Autodesk Fusion 360 part; units mm, degrees
(part 2 of 3)
ref_plane "WorkPlane21" through (0, 0, 1.55) normal (0, 0, 1) x (1, 0, 0) in component "02 Rear cover - ESP32 mounting and concealed button access"
sketch "right lower rear registration key profile" plane through (0, 0, 1.55) normal (0, 0, 1) x (1, 0, 0) in component "02 Rear cover - ESP32 mounting and concealed button access"
  line L0 (24.61, -15.45) -> (25.86, -15.45)
  line L1 (25.86, -15.45) -> (25.86, -12.85)
  line L2 (25.86, -12.85) -> (24.61, -12.85)
  line L3 (24.61, -12.85) -> (24.61, -15.45)
  dimension "d485" = 24.61
  dimension "d486" = 15.45
  dimension "d487" = 1.25
  dimension "d488" = 2.6
  constraint horizontal L0
  constraint horizontal L2
  constraint vertical L1
  constraint vertical L3
  measures "d485" horizontal distance of origin L0.start
  measures "d486" vertical distance of origin L0.start
  measures "d487" horizontal distance of L0.start L0.end
  measures "d488" vertical distance of L0.end L1.end
extrude "right lower rear registration key" add sketch "right lower rear registration key profile" along normal blind 1.15 bodies 2 in component "02 Rear cover - ESP32 mounting and concealed button access"
ref_plane "WorkPlane22" through (0, 0, 1.55) normal (0, 0, 1) x (1, 0, 0) in component "02 Rear cover - ESP32 mounting and concealed button access"
sketch "right upper rear registration key profile" plane through (0, 0, 1.55) normal (0, 0, 1) x (1, 0, 0) in component "02 Rear cover - ESP32 mounting and concealed button access"
  line L0 (24.61, 12.85) -> (25.86, 12.85)
  line L1 (25.86, 12.85) -> (25.86, 15.45)
  line L2 (25.86, 15.45) -> (24.61, 15.45)
  line L3 (24.61, 15.45) -> (24.61, 12.85)
  dimension "d493" = 24.61
  dimension "d494" = 12.85
  dimension "d495" = 1.25
  dimension "d496" = 2.6
  constraint horizontal L0
  constraint horizontal L2
  constraint vertical L1
  constraint vertical L3
  measures "d493" horizontal distance of origin L0.start
  measures "d494" vertical distance of origin L0.start
  measures "d495" horizontal distance of L0.start L0.end
  measures "d496" vertical distance of L0.end L1.end
extrude "right upper rear registration key" add sketch "right upper rear registration key profile" along normal blind 1.15 bodies 2 in component "02 Rear cover - ESP32 mounting and concealed button access"
sketch "USB-C plug relief at rear edge profile" plane through (0, 0, 0) normal (0, 0, 1) x (1, 0, 0) in component "02 Rear cover - ESP32 mounting and concealed button access"
  line L0 (26.81, -7) -> (28.71, -7)
  line L1 (28.71, -7) -> (28.71, 7)
  line L2 (28.71, 7) -> (26.81, 7)
  line L3 (26.81, 7) -> (26.81, -7)
  dimension "d499" = 26.81
  dimension "d500" = 7
  dimension "d501" = 1.9
  dimension "d502" = 14
  constraint horizontal L0
  constraint horizontal L2
  constraint vertical L1
  constraint vertical L3
  measures "d499" horizontal distance of origin L0.start
  measures "d500" vertical distance of origin L0.start
  measures "d501" horizontal distance of L0.start L0.end
  measures "d502" vertical distance of L0.end L1.end
extrude "USB-C plug relief at rear edge" cut sketch "USB-C plug relief at rear edge profile" along normal blind 1.55 bodies 2 in component "02 Rear cover - ESP32 mounting and concealed button access"
ref_plane "WorkPlane1" through (0, 0, 12.25) normal (0, 0, 1) x (1, 0, 0) in component "90 Reference - Handson DSP1170 4-pin OLED"
sketch "OLED carrier PCB profile" plane through (0, 0, 12.25) normal (0, 0, 1) x (1, 0, 0) in component "90 Reference - Handson DSP1170 4-pin OLED"
  line L0 (-17.7, -16.75) -> (17.7, -16.75)
  line L1 (17.7, -16.75) -> (17.7, 16.75)
  line L2 (17.7, 16.75) -> (-17.7, 16.75)
  line L3 (-17.7, 16.75) -> (-17.7, -16.75)
  dimension "d507" = 17.7
  dimension "d508" = 16.75
  dimension "d509" = 35.4
  dimension "d510" = 33.5
  constraint horizontal L0
  constraint horizontal L2
  constraint vertical L1
  constraint vertical L3
  measures "d507" horizontal distance of origin L0.start
  measures "d508" vertical distance of origin L0.start
  measures "d509" horizontal distance of L0.start L0.end
  measures "d510" vertical distance of L0.end L1.end
extrude "OLED carrier PCB" add sketch "OLED carrier PCB profile" along normal blind 1.2 separate body makes body 3 in component "90 Reference - Handson DSP1170 4-pin OLED"
ref_plane "WorkPlane2" through (0, 0, 12.25) normal (0, 0, 1) x (1, 0, 0) in component "90 Reference - Handson DSP1170 4-pin OLED"
sketch "OLED mounting holes 1 profile" plane through (0, 0, 12.25) normal (0, 0, 1) x (1, 0, 0) in component "90 Reference - Handson DSP1170 4-pin OLED"
  circle A0 centre (-15.2, -14.25) radius 1.25
  dimension "d515" = 15.2
  dimension "d516" = 14.25
  dimension "d517" = 2.5
  measures "d515" horizontal distance of origin A0.centre
  measures "d516" vertical distance of origin A0.centre
  measures "d517" diameter of A0
extrude "OLED mounting holes 1" cut sketch "OLED mounting holes 1 profile" along normal blind 1.2 bodies 3 in component "90 Reference - Handson DSP1170 4-pin OLED"
ref_plane "WorkPlane3" through (0, 0, 12.25) normal (0, 0, 1) x (1, 0, 0) in component "90 Reference - Handson DSP1170 4-pin OLED"
sketch "OLED mounting holes 2 profile" plane through (0, 0, 12.25) normal (0, 0, 1) x (1, 0, 0) in component "90 Reference - Handson DSP1170 4-pin OLED"
  circle A0 centre (-15.2, 14.25) radius 1.25
  dimension "d522" = 15.2
  dimension "d523" = 14.25
  dimension "d524" = 2.5
  measures "d522" horizontal distance of origin A0.centre
  measures "d523" vertical distance of origin A0.centre
  measures "d524" diameter of A0
extrude "OLED mounting holes 2" cut sketch "OLED mounting holes 2 profile" along normal blind 1.2 bodies 3 in component "90 Reference - Handson DSP1170 4-pin OLED"
ref_plane "WorkPlane4" through (0, 0, 12.25) normal (0, 0, 1) x (1, 0, 0) in component "90 Reference - Handson DSP1170 4-pin OLED"
sketch "OLED mounting holes 3 profile" plane through (0, 0, 12.25) normal (0, 0, 1) x (1, 0, 0) in component "90 Reference - Handson DSP1170 4-pin OLED"
  circle A0 centre (15.2, -14.25) radius 1.25
  dimension "d529" = 15.2
  dimension "d530" = 14.25
  dimension "d531" = 2.5
  measures "d529" horizontal distance of origin A0.centre
  measures "d530" vertical distance of origin A0.centre
  measures "d531" diameter of A0
extrude "OLED mounting holes 3" cut sketch "OLED mounting holes 3 profile" along normal blind 1.2 bodies 3 in component "90 Reference - Handson DSP1170 4-pin OLED"
ref_plane "WorkPlane5" through (0, 0, 12.25) normal (0, 0, 1) x (1, 0, 0) in component "90 Reference - Handson DSP1170 4-pin OLED"
sketch "OLED mounting holes 4 profile" plane through (0, 0, 12.25) normal (0, 0, 1) x (1, 0, 0) in component "90 Reference - Handson DSP1170 4-pin OLED"
  circle A0 centre (15.2, 14.25) radius 1.25
  dimension "d536" = 15.2
  dimension "d537" = 14.25
  dimension "d538" = 2.5
  measures "d536" horizontal distance of origin A0.centre
  measures "d537" vertical distance of origin A0.centre
  measures "d538" diameter of A0
extrude "OLED mounting holes 4" cut sketch "OLED mounting holes 4 profile" along normal blind 1.2 bodies 3 in component "90 Reference - Handson DSP1170 4-pin OLED"
ref_plane "WorkPlane6" through (0, 0, 13.45) normal (0, 0, 1) x (1, 0, 0) in component "90 Reference - Handson DSP1170 4-pin OLED"
sketch "OLED glass envelope profile" plane through (0, 0, 13.45) normal (0, 0, 1) x (1, 0, 0) in component "90 Reference - Handson DSP1170 4-pin OLED"
  line L0 (-17.25, -11.5) -> (17.25, -11.5)
  line L1 (17.25, -11.5) -> (17.25, 11.5)
  line L2 (17.25, 11.5) -> (-17.25, 11.5)
  line L3 (-17.25, 11.5) -> (-17.25, -11.5)
  dimension "d543" = 17.25
  dimension "d544" = 11.5
  dimension "d545" = 34.5
  dimension "d546" = 23
  constraint horizontal L0
  constraint horizontal L2
  constraint vertical L1
  constraint vertical L3
  measures "d543" horizontal distance of origin L0.start
  measures "d544" vertical distance of origin L0.start
  measures "d545" horizontal distance of L0.start L0.end
  measures "d546" vertical distance of L0.end L1.end
extrude "OLED glass envelope" add sketch "OLED glass envelope profile" along normal blind 1.9 separate body makes body 4 in component "90 Reference - Handson DSP1170 4-pin OLED"
ref_plane "WorkPlane7" through (0, 0, 11.25) normal (0, 0, 1) x (1, 0, 0) in component "90 Reference - Handson DSP1170 4-pin OLED"
sketch "Four soldered leads and bends profile" plane through (0, 0, 11.25) normal (0, 0, 1) x (1, 0, 0) in component "90 Reference - Handson DSP1170 4-pin OLED"
  line L0 (-5.08, 13.55) -> (5.08, 13.55)
  line L1 (5.08, 13.55) -> (5.08, 15.95)
  line L2 (5.08, 15.95) -> (-5.08, 15.95)
  line L3 (-5.08, 15.95) -> (-5.08, 13.55)
  dimension "d551" = 5.08
  dimension "d552" = 13.55
  dimension "d553" = 10.16
  dimension "d554" = 2.4
  constraint horizontal L0
  constraint horizontal L2
  constraint vertical L1
  constraint vertical L3
  measures "d551" horizontal distance of origin L0.start
  measures "d552" vertical distance of origin L0.start
  measures "d553" horizontal distance of L0.start L0.end
  measures "d554" vertical distance of L0.end L1.end
extrude "Four soldered leads and bends" add sketch "Four soldered leads and bends profile" along normal blind 1 separate body makes body 5 in component "90 Reference - Handson DSP1170 4-pin OLED"
ref_plane "WorkPlane1" through (0, 0, 5.15) normal (0, 0, 1) x (1, 0, 0) in component "91 Reference - nominal headerless USB-C ESP32"
sketch "ESP32 PCB outline profile" plane through (0, 0, 5.15) normal (0, 0, 1) x (1, 0, 0) in component "91 Reference - nominal headerless USB-C ESP32"
  line L0 (-25.86, -13.97) -> (25.86, -13.97)
  line L1 (25.86, -13.97) -> (25.86, 13.97)
  line L2 (25.86, 13.97) -> (-25.86, 13.97)
  line L3 (-25.86, 13.97) -> (-25.86, -13.97)
  dimension "d559" = 25.86
  dimension "d560" = 13.97
  dimension "d561" = 51.72
  dimension "d562" = 27.94
  constraint horizontal L0
  constraint horizontal L2
  constraint vertical L1
  constraint vertical L3
  measures "d559" horizontal distance of origin L0.start
  measures "d560" vertical distance of origin L0.start
  measures "d561" horizontal distance of L0.start L0.end
  measures "d562" vertical distance of L0.end L1.end
extrude "ESP32 PCB outline" add sketch "ESP32 PCB outline profile" along normal blind 1.6 separate body makes body 6 in component "91 Reference - nominal headerless USB-C ESP32"
ref_plane "WorkPlane2" through (0, 0, 5.15) normal (0, 0, 1) x (1, 0, 0) in component "91 Reference - nominal headerless USB-C ESP32"
sketch "ESP32 mounting holes 1 profile" plane through (0, 0, 5.15) normal (0, 0, 1) x (1, 0, 0) in component "91 Reference - nominal headerless USB-C ESP32"
  circle A0 centre (-23.09, -11.2) radius 1.5
  dimension "d567" = 23.09
  dimension "d568" = 11.2
  dimension "d569" = 3
  measures "d567" horizontal distance of origin A0.centre
  measures "d568" vertical distance of origin A0.centre
  measures "d569" diameter of A0
extrude "ESP32 mounting holes 1" cut sketch "ESP32 mounting holes 1 profile" along normal blind 1.6 bodies 6 in component "91 Reference - nominal headerless USB-C ESP32"
ref_plane "WorkPlane3" through (0, 0, 5.15) normal (0, 0, 1) x (1, 0, 0) in component "91 Reference - nominal headerless USB-C ESP32"
sketch "ESP32 mounting holes 2 profile" plane through (0, 0, 5.15) normal (0, 0, 1) x (1, 0, 0) in component "91 Reference - nominal headerless USB-C ESP32"
  circle A0 centre (-23.09, 11.2) radius 1.5
  dimension "d574" = 23.09
  dimension "d575" = 11.2
  dimension "d576" = 3
  measures "d574" horizontal distance of origin A0.centre
  measures "d575" vertical distance of origin A0.centre
  measures "d576" diameter of A0
extrude "ESP32 mounting holes 2" cut sketch "ESP32 mounting holes 2 profile" along normal blind 1.6 bodies 6 in component "91 Reference - nominal headerless USB-C ESP32"
ref_plane "WorkPlane4" through (0, 0, 5.15) normal (0, 0, 1) x (1, 0, 0) in component "91 Reference - nominal headerless USB-C ESP32"
sketch "ESP32 mounting holes 3 profile" plane through (0, 0, 5.15) normal (0, 0, 1) x (1, 0, 0) in component "91 Reference - nominal headerless USB-C ESP32"
  circle A0 centre (23.09, -11.2) radius 1.5
  dimension "d581" = 23.09
  dimension "d582" = 11.2
  dimension "d583" = 3
  measures "d581" horizontal distance of origin A0.centre
  measures "d582" vertical distance of origin A0.centre
  measures "d583" diameter of A0
extrude "ESP32 mounting holes 3" cut sketch "ESP32 mounting holes 3 profile" along normal blind 1.6 bodies 6 in component "91 Reference - nominal headerless USB-C ESP32"
ref_plane "WorkPlane5" through (0, 0, 5.15) normal (0, 0, 1) x (1, 0, 0) in component "91 Reference - nominal headerless USB-C ESP32"
sketch "ESP32 mounting holes 4 profile" plane through (0, 0, 5.15) normal (0, 0, 1) x (1, 0, 0) in component "91 Reference - nominal headerless USB-C ESP32"
  circle A0 centre (23.09, 11.2) radius 1.5
  dimension "d588" = 23.09
  dimension "d589" = 11.2
  dimension "d590" = 3
  measures "d588" horizontal distance of origin A0.centre
  measures "d589" vertical distance of origin A0.centre
  measures "d590" diameter of A0
extrude "ESP32 mounting holes 4" cut sketch "ESP32 mounting holes 4 profile" along normal blind 1.6 bodies 6 in component "91 Reference - nominal headerless USB-C ESP32"
ref_plane "WorkPlane6" through (0, 0, 1.95) normal (0, 0, 1) x (1, 0, 0) in component "91 Reference - nominal headerless USB-C ESP32"
sketch "ESP32-WROOM shield envelope profile" plane through (0, 0, 1.95) normal (0, 0, 1) x (1, 0, 0) in component "91 Reference - nominal headerless USB-C ESP32"
  line L0 (-19.86, -9) -> (-0.36, -9)
  line L1 (-0.36, -9) -> (-0.36, 9)
  line L2 (-0.36, 9) -> (-19.86, 9)
  line L3 (-19.86, 9) -> (-19.86, -9)
  dimension "d595" = 19.86
  dimension "d596" = 9
  dimension "d597" = 19.5
  dimension "d598" = 18
  constraint horizontal L0
  constraint horizontal L2
  constraint vertical L1
  constraint vertical L3
  measures "d595" horizontal distance of origin L0.start
  measures "d596" vertical distance of origin L0.start
  measures "d597" horizontal distance of L0.start L0.end
  measures "d598" vertical distance of L0.end L1.end
extrude "ESP32-WROOM shield envelope" add sketch "ESP32-WROOM shield envelope profile" along normal blind 3.2 separate body makes body 7 in component "91 Reference - nominal headerless USB-C ESP32"
ref_plane "WorkPlane7" through (0, 0, 4.25) normal (0, 0, 1) x (1, 0, 0) in component "91 Reference - nominal headerless USB-C ESP32"
sketch "ESP32-WROOM antenna laminate profile" plane through (0, 0, 4.25) normal (0, 0, 1) x (1, 0, 0) in component "91 Reference - nominal headerless USB-C ESP32"
  line L0 (-25.86, -9) -> (-19.86, -9)
  line L1 (-19.86, -9) -> (-19.86, 9)
  line L2 (-19.86, 9) -> (-25.86, 9)
  line L3 (-25.86, 9) -> (-25.86, -9)
  dimension "d603" = 25.86
  dimension "d604" = 9
  dimension "d605" = 6
  dimension "d606" = 18
  constraint horizontal L0
  constraint horizontal L2
  constraint vertical L1
  constraint vertical L3
  measures "d603" horizontal distance of origin L0.start
  measures "d604" vertical distance of origin L0.start
  measures "d605" horizontal distance of L0.start L0.end
  measures "d606" vertical distance of L0.end L1.end
extrude "ESP32-WROOM antenna laminate" add sketch "ESP32-WROOM antenna laminate profile" along normal blind 0.9 separate body makes body 8 in component "91 Reference - nominal headerless USB-C ESP32"
ref_plane "WorkPlane8" through (0, 0, 1.85) normal (0, 0, 1) x (1, 0, 0) in component "91 Reference - nominal headerless USB-C ESP32"
sketch "USB-C receptacle envelope profile" plane through (0, 0, 1.85) normal (0, 0, 1) x (1, 0, 0) in component "91 Reference - nominal headerless USB-C ESP32"
  line L0 (19.66, -4.62) -> (27.46, -4.62)
  line L1 (27.46, -4.62) -> (27.46, 4.62)
  line L2 (27.46, 4.62) -> (19.66, 4.62)
  line L3 (19.66, 4.62) -> (19.66, -4.62)
  dimension "d611" = 19.66
  dimension "d612" = 4.62
  dimension "d613" = 7.8
  dimension "d614" = 9.24
  constraint horizontal L0
  constraint horizontal L2
  constraint vertical L1
  constraint vertical L3
  measures "d611" horizontal distance of origin L0.start
  measures "d612" vertical distance of origin L0.start
  measures "d613" horizontal distance of L0.start L0.end
  measures "d614" vertical distance of L0.end L1.end
extrude "USB-C receptacle envelope" add sketch "USB-C receptacle envelope profile" along normal blind 3.3 separate body makes body 9 in component "91 Reference - nominal headerless USB-C ESP32"
ref_plane "WorkPlane9" through (0, 0, 2.7) normal (0, 0, 1) x (1, 0, 0) in component "91 Reference - nominal headerless USB-C ESP32"
sketch "BOOT switch envelope profile" plane through (0, 0, 2.7) normal (0, 0, 1) x (1, 0, 0) in component "91 Reference - nominal headerless USB-C ESP32"
  line L0 (21.06, -8.9) -> (24.66, -8.9)
  line L1 (24.66, -8.9) -> (24.66, -6.3)
  line L2 (24.66, -6.3) -> (21.06, -6.3)
  line L3 (21.06, -6.3) -> (21.06, -8.9)
  dimension "d619" = 21.06
  dimension "d620" = 8.9
  dimension "d621" = 3.6
  dimension "d622" = 2.6
  constraint horizontal L0
  constraint horizontal L2
  constraint vertical L1
  constraint vertical L3
  measures "d619" horizontal distance of origin L0.start
  measures "d620" vertical distance of origin L0.start
  measures "d621" horizontal distance of L0.start L0.end
  measures "d622" vertical distance of L0.end L1.end
extrude "BOOT switch envelope" add sketch "BOOT switch envelope profile" along normal blind 2.45 separate body makes body 10 in component "91 Reference - nominal headerless USB-C ESP32"
ref_plane "WorkPlane10" through (0, 0, 2.7) normal (0, 0, 1) x (1, 0, 0) in component "91 Reference - nominal headerless USB-C ESP32"
sketch "EN switch envelope profile" plane through (0, 0, 2.7) normal (0, 0, 1) x (1, 0, 0) in component "91 Reference - nominal headerless USB-C ESP32"
  line L0 (21.06, 6.3) -> (24.66, 6.3)
  line L1 (24.66, 6.3) -> (24.66, 8.9)
  line L2 (24.66, 8.9) -> (21.06, 8.9)
  line L3 (21.06, 8.9) -> (21.06, 6.3)
  dimension "d627" = 21.06
  dimension "d628" = 6.3
  dimension "d629" = 3.6
  dimension "d630" = 2.6
  constraint horizontal L0
  constraint horizontal L2
  constraint vertical L1
  constraint vertical L3
  measures "d627" horizontal distance of origin L0.start
  measures "d628" vertical distance of origin L0.start
  measures "d629" horizontal distance of L0.start L0.end
  measures "d630" vertical distance of L0.end L1.end
extrude "EN switch envelope" add sketch "EN switch envelope profile" along normal blind 2.45 separate body makes body 11 in component "91 Reference - nominal headerless USB-C ESP32"
ref_plane "WorkPlane26" through (0, 0, 15.55) normal (0, 0, 1) x (1, 0, 0) in component "01 Beveled front - four blind OLED screw bosses"
sketch "Display mask hides PCB and four-wire connection profile" plane through (0, 0, 15.55) normal (0, 0, 1) x (1, 0, 0) in component "01 Beveled front - four blind OLED screw bosses"
  line L0 (-15.61, -10.05) -> (15.61, -10.05)
  line L1 (15.61, -10.05) -> (15.61, 6.45)
  line L2 (15.61, 6.45) -> (-15.61, 6.45)
  line L3 (-15.61, 6.45) -> (-15.61, -10.05)
  dimension "d640" = 15.61
  dimension "d641" = 10.05
  dimension "d642" = 31.22
  dimension "d643" = 16.5
  constraint horizontal L0
  constraint horizontal L2
  constraint vertical L1
  constraint vertical L3
  measures "d640" horizontal distance of origin L0.start
  measures "d641" vertical distance of origin L0.start
  measures "d642" horizontal distance of L0.start L0.end
  measures "d643" vertical distance of L0.end L1.end
extrude "Display mask hides PCB and four-wire connection" cut sketch "Display mask hides PCB and four-wire connection profile" along normal blind 3 bodies 1 in component "01 Beveled front - four blind OLED screw bosses"
ref_plane "WorkPlane27" through (0, 0, 13.45) normal (0, 0, 1) x (1, 0, 0) in component "01 Beveled front - four blind OLED screw bosses"
sketch "Blind M2 OLED mounting pilot 1 profile" plane through (0, 0, 13.45) normal (0, 0, 1) x (1, 0, 0) in component "01 Beveled front - four blind OLED screw bosses"
  circle A0 centre (-15.2, -14.25) radius 0.85
  dimension "d648" = 15.2
  dimension "d649" = 14.25
  dimension "d650" = 1.7
  measures "d648" horizontal distance of origin A0.centre
  measures "d649" vertical distance of origin A0.centre
  measures "d650" diameter of A0
extrude "Blind M2 OLED mounting pilot 1" cut sketch "Blind M2 OLED mounting pilot 1 profile" along normal blind 4.1 bodies 1 in component "01 Beveled front - four blind OLED screw bosses"
ref_plane "WorkPlane28" through (0, 0, 13.45) normal (0, 0, 1) x (1, 0, 0) in component "01 Beveled front - four blind OLED screw bosses"
sketch "Blind M2 OLED mounting pilot 2 profile" plane through (0, 0, 13.45) normal (0, 0, 1) x (1, 0, 0) in component "01 Beveled front - four blind OLED screw bosses"
  circle A0 centre (-15.2, 14.25) radius 0.85
  dimension "d655" = 15.2
  dimension "d656" = 14.25
  dimension "d657" = 1.7
  measures "d655" horizontal distance of origin A0.centre
  measures "d656" vertical distance of origin A0.centre
  measures "d657" diameter of A0
extrude "Blind M2 OLED mounting pilot 2" cut sketch "Blind M2 OLED mounting pilot 2 profile" along normal blind 4.1 bodies 1 in component "01 Beveled front - four blind OLED screw bosses"
ref_plane "WorkPlane29" through (0, 0, 13.45) normal (0, 0, 1) x (1, 0, 0) in component "01 Beveled front - four blind OLED screw bosses"
sketch "Blind M2 OLED mounting pilot 3 profile" plane through (0, 0, 13.45) normal (0, 0, 1) x (1, 0, 0) in component "01 Beveled front - four blind OLED screw bosses"
  circle A0 centre (15.2, -14.25) radius 0.85
  dimension "d662" = 15.2
  dimension "d663" = 14.25
  dimension "d664" = 1.7
  measures "d662" horizontal distance of origin A0.centre
  measures "d663" vertical distance of origin A0.centre
  measures "d664" diameter of A0
extrude "Blind M2 OLED mounting pilot 3" cut sketch "Blind M2 OLED mounting pilot 3 profile" along normal blind 4.1 bodies 1 in component "01 Beveled front - four blind OLED screw bosses"
ref_plane "WorkPlane30" through (0, 0, 13.45) normal (0, 0, 1) x (1, 0, 0) in component "01 Beveled front - four blind OLED screw bosses"
sketch "Blind M2 OLED mounting pilot 4 profile" plane through (0, 0, 13.45) normal (0, 0, 1) x (1, 0, 0) in component "01 Beveled front - four blind OLED screw bosses"
  circle A0 centre (15.2, 14.25) radius 0.85
  dimension "d669" = 15.2
  dimension "d670" = 14.25
  dimension "d671" = 1.7
  measures "d669" horizontal distance of origin A0.centre
  measures "d670" vertical distance of origin A0.centre
  measures "d671" diameter of A0
extrude "Blind M2 OLED mounting pilot 4" cut sketch "Blind M2 OLED mounting pilot 4 profile" along normal blind 4.1 bodies 1 in component "01 Beveled front - four blind OLED screw bosses"
chamfer "Shallow sloped display reveal" distance 2.65 angle 45 4 edges at (0, 6.45, 18.55) (15.61, -1.8, 18.55) (0, -10.05, 18.55) (-15.61, -1.8, 18.55) tangent chain off on bodies 1 in component "01 Beveled front - four blind OLED screw bosses"
ref_plane "WorkPlane1" through (0, 0, 7.25) normal (0, 0, 1) x (1, 0, 0) in component "92 Reference - upper-bound M2 x 8 OLED screws"
sketch "OLED screw 1 head profile" plane through (0, 0, 7.25) normal (0, 0, 1) x (1, 0, 0) in component "92 Reference - upper-bound M2 x 8 OLED screws"
  circle A0 centre (-15.2, -14.25) radius 2
  dimension "d677" = 15.2
  dimension "d678" = 14.25
  dimension "d679" = 4
  measures "d677" horizontal distance of origin A0.centre
  measures "d678" vertical distance of origin A0.centre
  measures "d679" diameter of A0
extrude "OLED screw 1 head" add sketch "OLED screw 1 head profile" along normal blind 2 separate body makes body 12 in component "92 Reference - upper-bound M2 x 8 OLED screws"
ref_plane "WorkPlane2" through (0, 0, 9.25) normal (0, 0, 1) x (1, 0, 0) in component "92 Reference - upper-bound M2 x 8 OLED screws"
sketch "OLED screw 1 shank profile" plane through (0, 0, 9.25) normal (0, 0, 1) x (1, 0, 0) in component "92 Reference - upper-bound M2 x 8 OLED screws"
  circle A0 centre (-15.2, -14.25) radius 1
  dimension "d684" = 15.2
  dimension "d685" = 14.25
  dimension "d686" = 2
  measures "d684" horizontal distance of origin A0.centre
  measures "d685" vertical distance of origin A0.centre
  measures "d686" diameter of A0
extrude "OLED screw 1 shank" add sketch "OLED screw 1 shank profile" along normal blind 8 bodies 12 in component "92 Reference - upper-bound M2 x 8 OLED screws"
ref_plane "WorkPlane3" through (0, 0, 7.25) normal (0, 0, 1) x (1, 0, 0) in component "92 Reference - upper-bound M2 x 8 OLED screws"
sketch "OLED screw 2 head profile" plane through (0, 0, 7.25) normal (0, 0, 1) x (1, 0, 0) in component "92 Reference - upper-bound M2 x 8 OLED screws"
  circle A0 centre (-15.2, 14.25) radius 2
  dimension "d691" = 15.2
  dimension "d692" = 14.25
  dimension "d693" = 4
  measures "d691" horizontal distance of origin A0.centre
  measures "d692" vertical distance of origin A0.centre
  measures "d693" diameter of A0
extrude "OLED screw 2 head" add sketch "OLED screw 2 head profile" along normal blind 2 separate body makes body 13 in component "92 Reference - upper-bound M2 x 8 OLED screws"
ref_plane "WorkPlane4" through (0, 0, 9.25) normal (0, 0, 1) x (1, 0, 0) in component "92 Reference - upper-bound M2 x 8 OLED screws"
sketch "OLED screw 2 shank profile" plane through (0, 0, 9.25) normal (0, 0, 1) x (1, 0, 0) in component "92 Reference - upper-bound M2 x 8 OLED screws"
  circle A0 centre (-15.2, 14.25) radius 1
  dimension "d698" = 15.2
  dimension "d699" = 14.25
  dimension "d700" = 2
  measures "d698" horizontal distance of origin A0.centre
  measures "d699" vertical distance of origin A0.centre
  measures "d700" diameter of A0
extrude "OLED screw 2 shank" add sketch "OLED screw 2 shank profile" along normal blind 8 bodies 13 in component "92 Reference - upper-bound M2 x 8 OLED screws"
ref_plane "WorkPlane5" through (0, 0, 7.25) normal (0, 0, 1) x (1, 0, 0) in component "92 Reference - upper-bound M2 x 8 OLED screws"
sketch "OLED screw 3 head profile" plane through (0, 0, 7.25) normal (0, 0, 1) x (1, 0, 0) in component "92 Reference - upper-bound M2 x 8 OLED screws"
  circle A0 centre (15.2, -14.25) radius 2
  dimension "d705" = 15.2
  dimension "d706" = 14.25
  dimension "d707" = 4
  measures "d705" horizontal distance of origin A0.centre
  measures "d706" vertical distance of origin A0.centre
  measures "d707" diameter of A0
extrude "OLED screw 3 head" add sketch "OLED screw 3 head profile" along normal blind 2 separate body makes body 14 in component "92 Reference - upper-bound M2 x 8 OLED screws"
ref_plane "WorkPlane6" through (0, 0, 9.25) normal (0, 0, 1) x (1, 0, 0) in component "92 Reference - upper-bound M2 x 8 OLED screws"
sketch "OLED screw 3 shank profile" plane through (0, 0, 9.25) normal (0, 0, 1) x (1, 0, 0) in component "92 Reference - upper-bound M2 x 8 OLED screws"
  circle A0 centre (15.2, -14.25) radius 1
  dimension "d712" = 15.2
  dimension "d713" = 14.25
  dimension "d714" = 2
  measures "d712" horizontal distance of origin A0.centre
  measures "d713" vertical distance of origin A0.centre
  measures "d714" diameter of A0
extrude "OLED screw 3 shank" add sketch "OLED screw 3 shank profile" along normal blind 8 bodies 14 in component "92 Reference - upper-bound M2 x 8 OLED screws"
ref_plane "WorkPlane7" through (0, 0, 7.25) normal (0, 0, 1) x (1, 0, 0) in component "92 Reference - upper-bound M2 x 8 OLED screws"
sketch "OLED screw 4 head profile" plane through (0, 0, 7.25) normal (0, 0, 1) x (1, 0, 0) in component "92 Reference - upper-bound M2 x 8 OLED screws"
  circle A0 centre (15.2, 14.25) radius 2
  dimension "d719" = 15.2
  dimension "d720" = 14.25
  dimension "d721" = 4
  measures "d719" horizontal distance of origin A0.centre
  measures "d720" vertical distance of origin A0.centre
  measures "d721" diameter of A0
extrude "OLED screw 4 head" add sketch "OLED screw 4 head profile" along normal blind 2 separate body makes body 15 in component "92 Reference - upper-bound M2 x 8 OLED screws"
ref_plane "WorkPlane8" through (0, 0, 9.25) normal (0, 0, 1) x (1, 0, 0) in component "92 Reference - upper-bound M2 x 8 OLED screws"
sketch "OLED screw 4 shank profile" plane through (0, 0, 9.25) normal (0, 0, 1) x (1, 0, 0) in component "92 Reference - upper-bound M2 x 8 OLED screws"
  circle A0 centre (15.2, 14.25) radius 1
  dimension "d726" = 15.2
  dimension "d727" = 14.25
  dimension "d728" = 2
  measures "d726" horizontal distance of origin A0.centre
  measures "d727" vertical distance of origin A0.centre
  measures "d728" diameter of A0
extrude "OLED screw 4 shank" add sketch "OLED screw 4 shank profile" along normal blind 8 bodies 15 in component "92 Reference - upper-bound M2 x 8 OLED screws"
ref_plane "WorkPlane1" through (0, 0, 9.25) normal (0, 0, 1) x (1, 0, 0) in component "03 PRINT - OLED spacer rail 1"
sketch "Spacer connecting rail profile" plane through (0, 0, 9.25) normal (0, 0, 1) x (1, 0, 0) in component "03 PRINT - OLED spacer rail 1"
  line L0 (-15.2, -14.25) -> (-13.1, -14.25)
  line L1 (-13.1, -14.25) -> (-13.1, 14.25)
  line L2 (-13.1, 14.25) -> (-15.2, 14.25)
  line L3 (-15.2, 14.25) -> (-15.2, -14.25)
  dimension "d741" = 15.2
  dimension "d742" = 14.25
  dimension "d743" = 2.1
  dimension "d744" = 28.5
  constraint horizontal L0
  constraint horizontal L2
  constraint vertical L1
  constraint vertical L3
  measures "d741" horizontal distance of origin L0.start
  measures "d742" vertical distance of origin L0.start
  measures "d743" horizontal distance of L0.start L0.end
  measures "d744" vertical distance of L0.end L1.end
extrude "Spacer connecting rail" add sketch "Spacer connecting rail profile" along normal blind 1.4 separate body makes body 16 in component "03 PRINT - OLED spacer rail 1"
ref_plane "WorkPlane2" through (0, 0, 9.25) normal (0, 0, 1) x (1, 0, 0) in component "03 PRINT - OLED spacer rail 1"
sketch "OLED PCB spacer lands 1 profile" plane through (0, 0, 9.25) normal (0, 0, 1) x (1, 0, 0) in component "03 PRINT - OLED spacer rail 1"
  circle A0 centre (-15.2, -14.25) radius 2.3
  dimension "d749" = 15.2
  dimension "d750" = 14.25
  dimension "d751" = 4.6
  measures "d749" horizontal distance of origin A0.centre
  measures "d750" vertical distance of origin A0.centre
  measures "d751" diameter of A0
extrude "OLED PCB spacer lands 1" add sketch "OLED PCB spacer lands 1 profile" along normal blind 3 bodies 16 in component "03 PRINT - OLED spacer rail 1"
ref_plane "WorkPlane3" through (0, 0, 9.25) normal (0, 0, 1) x (1, 0, 0) in component "03 PRINT - OLED spacer rail 1"
sketch "OLED PCB spacer lands 2 profile" plane through (0, 0, 9.25) normal (0, 0, 1) x (1, 0, 0) in component "03 PRINT - OLED spacer rail 1"
  circle A0 centre (-15.2, 14.25) radius 2.3
  dimension "d756" = 15.2
  dimension "d757" = 14.25
  dimension "d758" = 4.6
  measures "d756" horizontal distance of origin A0.centre
  measures "d757" vertical distance of origin A0.centre
  measures "d758" diameter of A0
extrude "OLED PCB spacer lands 2" add sketch "OLED PCB spacer lands 2 profile" along normal blind 3 bodies 16 in component "03 PRINT - OLED spacer rail 1"
ref_plane "WorkPlane4" through (0, 0, 9.25) normal (0, 0, 1) x (1, 0, 0) in component "03 PRINT - OLED spacer rail 1"
sketch "M2 clearance through spacer rail 1 profile" plane through (0, 0, 9.25) normal (0, 0, 1) x (1, 0, 0) in component "03 PRINT - OLED spacer rail 1"
  circle A0 centre (-15.2, -14.25) radius 1.175
  dimension "d763" = 15.2
  dimension "d764" = 14.25
  dimension "d765" = 2.35
  measures "d763" horizontal distance of origin A0.centre
  measures "d764" vertical distance of origin A0.centre
  measures "d765" diameter of A0
extrude "M2 clearance through spacer rail 1" cut sketch "M2 clearance through spacer rail 1 profile" along normal blind 3 bodies 16 in component "03 PRINT - OLED spacer rail 1"
ref_plane "WorkPlane5" through (0, 0, 9.25) normal (0, 0, 1) x (1, 0, 0) in component "03 PRINT - OLED spacer rail 1"
sketch "M2 clearance through spacer rail 2 profile" plane through (0, 0, 9.25) normal (0, 0, 1) x (1, 0, 0) in component "03 PRINT - OLED spacer rail 1"
  circle A0 centre (-15.2, 14.25) radius 1.175
  dimension "d770" = 15.2
  dimension "d771" = 14.25
  dimension "d772" = 2.35
  measures "d770" horizontal distance of origin A0.centre
  measures "d771" vertical distance of origin A0.centre
  measures "d772" diameter of A0
extrude "M2 clearance through spacer rail 2" cut sketch "M2 clearance through spacer rail 2 profile" along normal blind 3 bodies 16 in component "03 PRINT - OLED spacer rail 1"
ref_plane "WorkPlane1" through (0, 0, 9.25) normal (0, 0, 1) x (1, 0, 0) in component "04 PRINT - OLED spacer rail 2"
sketch "Spacer connecting rail profile (2)" plane through (0, 0, 9.25) normal (0, 0, 1) x (1, 0, 0) in component "04 PRINT - OLED spacer rail 2"
  line L0 (13.1, -14.25) -> (15.2, -14.25)
  line L1 (15.2, -14.25) -> (15.2, 14.25)
  line L2 (15.2, 14.25) -> (13.1, 14.25)
  line L3 (13.1, 14.25) -> (13.1, -14.25)
  dimension "d777" = 13.1
  dimension "d778" = 14.25
  dimension "d779" = 2.1
  dimension "d780" = 28.5
  constraint horizontal L0
  constraint horizontal L2
  constraint vertical L1
  constraint vertical L3
  measures "d777" horizontal distance of origin L0.start
  measures "d778" vertical distance of origin L0.start
  measures "d779" horizontal distance of L0.start L0.end
  measures "d780" vertical distance of L0.end L1.end
extrude "Spacer connecting rail'" add sketch "Spacer connecting rail profile (2)" along normal blind 1.4 separate body makes body 17 in component "04 PRINT - OLED spacer rail 2"
ref_plane "WorkPlane2" through (0, 0, 9.25) normal (0, 0, 1) x (1, 0, 0) in component "04 PRINT - OLED spacer rail 2"
sketch "OLED PCB spacer lands 1 profile (2)" plane through (0, 0, 9.25) normal (0, 0, 1) x (1, 0, 0) in component "04 PRINT - OLED spacer rail 2"
  circle A0 centre (15.2, -14.25) radius 2.3
  dimension "d785" = 15.2
  dimension "d786" = 14.25
  dimension "d787" = 4.6
  measures "d785" horizontal distance of origin A0.centre
  measures "d786" vertical distance of origin A0.centre
  measures "d787" diameter of A0
extrude "OLED PCB spacer lands 1'" add sketch "OLED PCB spacer lands 1 profile (2)" along normal blind 3 bodies 17 in component "04 PRINT - OLED spacer rail 2"
ref_plane "WorkPlane3" through (0, 0, 9.25) normal (0, 0, 1) x (1, 0, 0) in component "04 PRINT - OLED spacer rail 2"
sketch "OLED PCB spacer lands 2 profile (2)" plane through (0, 0, 9.25) normal (0, 0, 1) x (1, 0, 0) in component "04 PRINT - OLED spacer rail 2"
  circle A0 centre (15.2, 14.25) radius 2.3
  dimension "d792" = 15.2
  dimension "d793" = 14.25
  dimension "d794" = 4.6
  measures "d792" horizontal distance of origin A0.centre
  measures "d793" vertical distance of origin A0.centre
  measures "d794" diameter of A0
extrude "OLED PCB spacer lands 2'" add sketch "OLED PCB spacer lands 2 profile (2)" along normal blind 3 bodies 17 in component "04 PRINT - OLED spacer rail 2"
ref_plane "WorkPlane4" through (0, 0, 9.25) normal (0, 0, 1) x (1, 0, 0) in component "04 PRINT - OLED spacer rail 2"
sketch "M2 clearance through spacer rail 1 profile (2)" plane through (0, 0, 9.25) normal (0, 0, 1) x (1, 0, 0) in component "04 PRINT - OLED spacer rail 2"
  circle A0 centre (15.2, -14.25) radius 1.175
  dimension "d799" = 15.2
  dimension "d800" = 14.25
  dimension "d801" = 2.35
  measures "d799" horizontal distance of origin A0.centre
  measures "d800" vertical distance of origin A0.centre
  measures "d801" diameter of A0
extrude "M2 clearance through spacer rail 1'" cut sketch "M2 clearance through spacer rail 1 profile (2)" along normal blind 3 bodies 17 in component "04 PRINT - OLED spacer rail 2"
ref_plane "WorkPlane5" through (0, 0, 9.25) normal (0, 0, 1) x (1, 0, 0) in component "04 PRINT - OLED spacer rail 2"
sketch "M2 clearance through spacer rail 2 profile (2)" plane through (0, 0, 9.25) normal (0, 0, 1) x (1, 0, 0) in component "04 PRINT - OLED spacer rail 2"
  circle A0 centre (15.2, 14.25) radius 1.175
  dimension "d806" = 15.2
  dimension "d807" = 14.25
  dimension "d808" = 2.35
  measures "d806" horizontal distance of origin A0.centre
  measures "d807" vertical distance of origin A0.centre
  measures "d808" diameter of A0
extrude "M2 clearance through spacer rail 2'" cut sketch "M2 clearance through spacer rail 2 profile (2)" along normal blind 3 bodies 17 in component "04 PRINT - OLED spacer rail 2"
ref_plane "WorkPlane31" through (0, 0, 13.95) normal (0, 0, 1) x (1, 0, 0) in component "01 Beveled front - four blind OLED screw bosses"
sketch "Covered cable recess beside display glass profile" plane through (0, 0, 13.95) normal (0, 0, 1) x (1, 0, 0) in component "01 Beveled front - four blind OLED screw bosses"
  line L0 (-6.5, 11.3) -> (6.5, 11.3)
  line L1 (6.5, 11.3) -> (6.5, 17)
  line L2 (6.5, 17) -> (-6.5, 17)
  line L3 (-6.5, 17) -> (-6.5, 11.3)
  dimension "d813" = 6.5
  dimension "d815" = 13
  dimension "d816" = 5.7
  constraint horizontal L0
  constraint horizontal L2
  constraint vertical L1
  constraint vertical L3
  measures "d813" horizontal distance of origin L0.start
  measures "d815" horizontal distance of L0.start L0.end
  measures "d816" vertical distance of L0.end L1.end
extrude "Covered cable recess beside display glass" cut sketch "Covered cable recess beside display glass profile" along normal blind 1.7 bodies 1 in component "01 Beveled front - four blind OLED screw bosses"
ref_plane "WorkPlane8" through (0, 0, 13.45) normal (0, 0, 1) x (1, 0, 0) in component "90 Reference - Handson DSP1170 4-pin OLED"
sketch "Front solder and cable height envelope profile" plane through (0, 0, 13.45) normal (0, 0, 1) x (1, 0, 0) in component "90 Reference - Handson DSP1170 4-pin OLED"
  line L0 (-5.08, 13.55) -> (5.08, 13.55)
  line L1 (5.08, 13.55) -> (5.08, 15.95)
  line L2 (5.08, 15.95) -> (-5.08, 15.95)
  line L3 (-5.08, 15.95) -> (-5.08, 13.55)
  dimension "d821" = 5.08
  dimension "d822" = 13.55
  dimension "d823" = 10.16
  dimension "d824" = 2.4
  constraint horizontal L0
  constraint horizontal L2
  constraint vertical L1
  constraint vertical L3
  measures "d821" horizontal distance of origin L0.start
  measures "d822" vertical distance of origin L0.start
  measures "d823" horizontal distance of L0.start L0.end
  measures "d824" vertical distance of L0.end L1.end
extrude "Front solder and cable height envelope" add sketch "Front solder and cable height envelope profile" along normal blind 1.9 separate body makes body 18 in component "90 Reference - Handson DSP1170 4-pin OLED"
ref_plane "WorkPlane23" through (0, 0, 2.65) normal (0, 0, 1) x (1, 0, 0) in component "02 Rear cover - ESP32 mounting and concealed button access"
sketch "BOOT clearance beside deeper screw foot profile" plane through (0, 0, 2.65) normal (0, 0, 1) x (1, 0, 0) in component "02 Rear cover - ESP32 mounting and concealed button access"
  line L0 (20.66, -9.15) -> (25.06, -9.15)
  line L1 (25.06, -9.15) -> (25.06, -6.05)
  line L2 (25.06, -6.05) -> (20.66, -6.05)
  line L3 (20.66, -6.05) -> (20.66, -9.15)
  dimension "d829" = 20.66
  dimension "d830" = 9.15
  dimension "d831" = 4.4
  dimension "d832" = 3.1
  constraint horizontal L0
  constraint horizontal L2
  constraint vertical L1
  constraint vertical L3
  measures "d829" horizontal distance of origin L0.start
  measures "d830" vertical distance of origin L0.start
  measures "d831" horizontal distance of L0.start L0.end
  measures "d832" vertical distance of L0.end L1.end
extrude "BOOT clearance beside deeper screw foot" cut sketch "BOOT clearance beside deeper screw foot profile" along normal blind 0.9 bodies 2 in component "02 Rear cover - ESP32 mounting and concealed button access"
ref_plane "WorkPlane24" through (0, 0, 2.65) normal (0, 0, 1) x (1, 0, 0) in component "02 Rear cover - ESP32 mounting and concealed button access"
sketch "EN clearance beside deeper screw foot profile" plane through (0, 0, 2.65) normal (0, 0, 1) x (1, 0, 0) in component "02 Rear cover - ESP32 mounting and concealed button access"
  line L0 (20.66, 6.05) -> (25.06, 6.05)
  line L1 (25.06, 6.05) -> (25.06, 9.15)
  line L2 (25.06, 9.15) -> (20.66, 9.15)
  line L3 (20.66, 9.15) -> (20.66, 6.05)
  dimension "d837" = 20.66
  dimension "d838" = 6.05
  dimension "d839" = 4.4
  dimension "d840" = 3.1
  constraint horizontal L0
  constraint horizontal L2
  constraint vertical L1
  constraint vertical L3
  measures "d837" horizontal distance of origin L0.start
  measures "d838" vertical distance of origin L0.start
  measures "d839" horizontal distance of L0.start L0.end
  measures "d840" vertical distance of L0.end L1.end
extrude "EN clearance beside deeper screw foot" cut sketch "EN clearance beside deeper screw foot profile" along normal blind 0.9 bodies 2 in component "02 Rear cover - ESP32 mounting and concealed button access"
ref_plane "WorkPlane1" through (0, 0, 0.85) normal (0, 0, 1) x (1, 0, 0) in component "93 Reference - upper-bound M2 x 8 rear screws"
sketch "Rear screw 1 head profile" plane through (0, 0, 0.85) normal (0, 0, 1) x (1, 0, 0) in component "93 Reference - upper-bound M2 x 8 rear screws"
  circle A0 centre (-23.09, -11.2) radius 2
  dimension "d845" = 23.09
  dimension "d846" = 11.2
  dimension "d847" = 4
  measures "d845" horizontal distance of origin A0.centre
  measures "d846" vertical distance of origin A0.centre
  measures "d847" diameter of A0
extrude "Rear screw 1 head" add sketch "Rear screw 1 head profile" along normal blind 2 separate body makes body 19 in component "93 Reference - upper-bound M2 x 8 rear screws"
ref_plane "WorkPlane2" through (0, 0, 2.85) normal (0, 0, 1) x (1, 0, 0) in component "93 Reference - upper-bound M2 x 8 rear screws"
sketch "Rear screw 1 shank profile" plane through (0, 0, 2.85) normal (0, 0, 1) x (1, 0, 0) in component "93 Reference - upper-bound M2 x 8 rear screws"
  circle A0 centre (-23.09, -11.2) radius 1
  dimension "d852" = 23.09
  dimension "d853" = 11.2
  dimension "d854" = 2
  measures "d852" horizontal distance of origin A0.centre
  measures "d853" vertical distance of origin A0.centre
  measures "d854" diameter of A0
extrude "Rear screw 1 shank" add sketch "Rear screw 1 shank profile" along normal blind 8 bodies 19 in component "93 Reference - upper-bound M2 x 8 rear screws"
ref_plane "WorkPlane3" through (0, 0, 0.85) normal (0, 0, 1) x (1, 0, 0) in component "93 Reference - upper-bound M2 x 8 rear screws"
sketch "Rear screw 2 head profile" plane through (0, 0, 0.85) normal (0, 0, 1) x (1, 0, 0) in component "93 Reference - upper-bound M2 x 8 rear screws"
  circle A0 centre (-23.09, 11.2) radius 2
  dimension "d859" = 23.09
  dimension "d860" = 11.2
  dimension "d861" = 4
  measures "d859" horizontal distance of origin A0.centre
  measures "d860" vertical distance of origin A0.centre
  measures "d861" diameter of A0
extrude "Rear screw 2 head" add sketch "Rear screw 2 head profile" along normal blind 2 separate body makes body 20 in component "93 Reference - upper-bound M2 x 8 rear screws"
ref_plane "WorkPlane4" through (0, 0, 2.85) normal (0, 0, 1) x (1, 0, 0) in component "93 Reference - upper-bound M2 x 8 rear screws"
sketch "Rear screw 2 shank profile" plane through (0, 0, 2.85) normal (0, 0, 1) x (1, 0, 0) in component "93 Reference - upper-bound M2 x 8 rear screws"
  circle A0 centre (-23.09, 11.2) radius 1
  dimension "d866" = 23.09
  dimension "d867" = 11.2
  dimension "d868" = 2
  measures "d866" horizontal distance of origin A0.centre
  measures "d867" vertical distance of origin A0.centre
  measures "d868" diameter of A0
extrude "Rear screw 2 shank" add sketch "Rear screw 2 shank profile" along normal blind 8 bodies 20 in component "93 Reference - upper-bound M2 x 8 rear screws"
ref_plane "WorkPlane5" through (0, 0, 0.85) normal (0, 0, 1) x (1, 0, 0) in component "93 Reference - upper-bound M2 x 8 rear screws"
sketch "Rear screw 3 head profile" plane through (0, 0, 0.85) normal (0, 0, 1) x (1, 0, 0) in component "93 Reference - upper-bound M2 x 8 rear screws"
  circle A0 centre (23.09, -11.2) radius 2
  dimension "d873" = 23.09
  dimension "d874" = 11.2
  dimension "d875" = 4
  measures "d873" horizontal distance of origin A0.centre
  measures "d874" vertical distance of origin A0.centre
  measures "d875" diameter of A0
extrude "Rear screw 3 head" add sketch "Rear screw 3 head profile" along normal blind 2 separate body makes body 21 in component "93 Reference - upper-bound M2 x 8 rear screws"
ref_plane "WorkPlane6" through (0, 0, 2.85) normal (0, 0, 1) x (1, 0, 0) in component "93 Reference - upper-bound M2 x 8 rear screws"
sketch "Rear screw 3 shank profile" plane through (0, 0, 2.85) normal (0, 0, 1) x (1, 0, 0) in component "93 Reference - upper-bound M2 x 8 rear screws"
  circle A0 centre (23.09, -11.2) radius 1
  dimension "d880" = 23.09
  dimension "d881" = 11.2
  dimension "d882" = 2
  measures "d880" horizontal distance of origin A0.centre
  measures "d881" vertical distance of origin A0.centre
  measures "d882" diameter of A0
extrude "Rear screw 3 shank" add sketch "Rear screw 3 shank profile" along normal blind 8 bodies 21 in component "93 Reference - upper-bound M2 x 8 rear screws"
ref_plane "WorkPlane7" through (0, 0, 0.85) normal (0, 0, 1) x (1, 0, 0) in component "93 Reference - upper-bound M2 x 8 rear screws"
sketch "Rear screw 4 head profile" plane through (0, 0, 0.85) normal (0, 0, 1) x (1, 0, 0) in component "93 Reference - upper-bound M2 x 8 rear screws"
  circle A0 centre (23.09, 11.2) radius 2
  dimension "d887" = 23.09
  dimension "d888" = 11.2
  dimension "d889" = 4
  measures "d887" horizontal distance of origin A0.centre
  measures "d888" vertical distance of origin A0.centre
  measures "d889" diameter of A0
extrude "Rear screw 4 head" add sketch "Rear screw 4 head profile" along normal blind 2 separate body makes body 22 in component "93 Reference - upper-bound M2 x 8 rear screws"
ref_plane "WorkPlane8" through (0, 0, 2.85) normal (0, 0, 1) x (1, 0, 0) in component "93 Reference - upper-bound M2 x 8 rear screws"
sketch "Rear screw 4 shank profile" plane through (0, 0, 2.85) normal (0, 0, 1) x (1, 0, 0) in component "93 Reference - upper-bound M2 x 8 rear screws"
  circle A0 centre (23.09, 11.2) radius 1
  dimension "d894" = 23.09
  dimension "d895" = 11.2
  dimension "d896" = 2
  measures "d894" horizontal distance of origin A0.centre
  measures "d895" vertical distance of origin A0.centre
  measures "d896" diameter of A0
extrude "Rear screw 4 shank" add sketch "Rear screw 4 shank profile" along normal blind 8 bodies 22 in component "93 Reference - upper-bound M2 x 8 rear screws"
component "01 Beveled front - four blind OLED screw bosses" placed x (1, 0, 0) y (0, 1, 0) z (0, 0, 1) at (0, 0, 0)
component "02 Rear cover - ESP32 mounting and concealed button access" placed x (1, 0, 0) y (0, 1, 0) z (0, 0, 1) at (0, 0, 0)
component "90 Reference - Handson DSP1170 4-pin OLED" placed x (1, 0, 0) y (0, 1, 0) z (0, 0, 1) at (0, 0, 0)
component "91 Reference - nominal headerless USB-C ESP32" placed x (1, 0, 0) y (0, 1, 0) z (0, 0, 1) at (0, 0, 0)
component "92 Reference - upper-bound M2 x 8 OLED screws" placed x (1, 0, 0) y (0, 1, 0) z (0, 0, 1) at (0, 0, 0)
component "03 PRINT - OLED spacer rail 1" placed x (1, 0, 0) y (0, 1, 0) z (0, 0, 1) at (0, 0, 0)
component "04 PRINT - OLED spacer rail 2" placed x (1, 0, 0) y (0, 1, 0) z (0, 0, 1) at (0, 0, 0)
component "93 Reference - upper-bound M2 x 8 rear screws" placed x (1, 0, 0) y (0, 1, 0) z (0, 0, 1) at (0, 0, 0)
hidden bodies 5 18
equation "espL = 51.72 mm" comment "Nominal 30-pin USB-C DevKit PCB, KiCad footprint"
equation "espW = 27.94 mm" comment "Nominal 30-pin USB-C DevKit PCB, KiCad footprint"
equation "espT = 1.6 mm" comment "Nominal ESP32 PCB thickness"
equation "espHoleX = 46.18 mm" comment "Generic USB-C DevKit mounting pitch along length"
equation "espHoleY = 22.4 mm" comment "Generic USB-C DevKit mounting pitch across board"
equation "espHoleD = 3 mm" comment "Nominal PCB hole diameter from the KiCad footprint"
equation "espSeat = 5.15 mm" comment "Component face toward rear cover"
equation "espBack = espSeat + espT" comment "ESP32 PCB back faces OLED PCB"
equation "espPartH = 3.2 mm" comment "Espressif WROOM-32 shield height incl. tolerance"
equation "espAntennaL = 6 mm" comment "Low-profile module antenna section, nominal"
equation "espButtonH = 2.45 mm" comment "Provisional plunger height above PCB"
equation "bootInset = 3 mm" comment "BOOT centre from connector-end PCB edge, photo estimate"
equation "enableInset = 3 mm" comment "EN centre from connector-end PCB edge, photo estimate"
equation "bootY = -7.6 mm" comment "BOOT transverse position, photo estimate"
equation "enableY = 7.6 mm" comment "EN transverse position, photo estimate"
equation "buttonGap = 0.5 mm" comment "Air gap between probe guide and switch"
equation "buttonBore = 1.6 mm" comment "Access for a blunt probe"
equation "buttonGuideD = 2.8 mm" comment "0.6 mm guide wall, clears recessed 4 mm screw heads beside switches"
equation "usbProtrusion = 1.6 mm" comment "Socket nose past PCB edge from KiCad footprint"
equation "usbShellW = 9.24 mm" comment "Nominal USB-C receptacle body width"
equation "usbShellH = 3.3 mm" comment "Nominal USB-C receptacle body height"
equation "usbY = 0 mm" comment "USB-C receptacle transverse centre"
equation "usbOpeningW = 14 mm" comment "Plug overmold clearance width"
equation "usbSlotTop = 7.3 mm" comment "Top of plug opening, above rear split"
equation "usbRearRelief = 0.9 mm" comment "Shallow plug relief in rear edge"